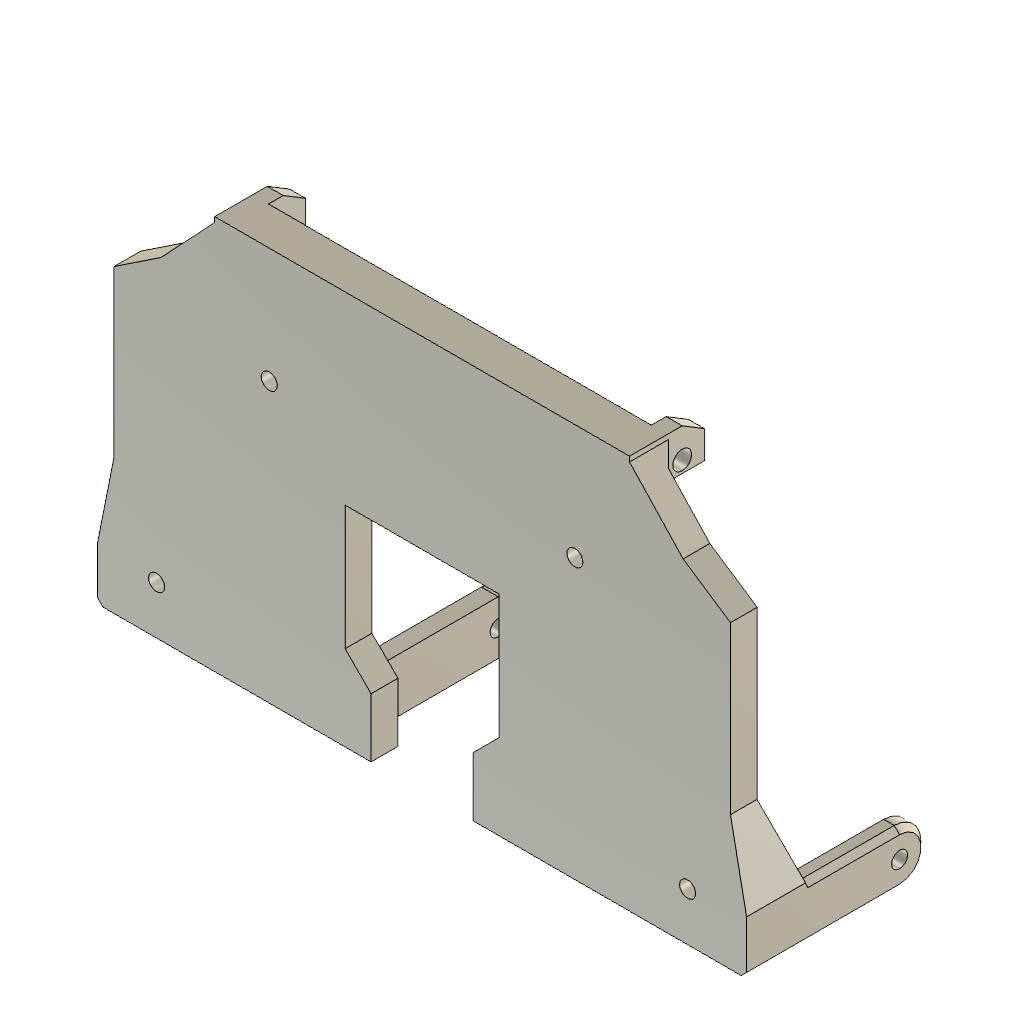
Main Base native (Autodesk Fusion 360 design; units mm, degrees)
part number: 2026-10-13-22-29-02-092
Autodesk Fusion 360 part; units mm, degrees
ref_plane "WorkPlane1" through (0, -26.0322, 0) normal (0, 1, 0) x (0, 0, 1)
sketch "Back plate" plane through (0, -26.0322, 0) normal (0, 1, 0) x (1, 0, 0)
  line L0 (-1.1848, -68.4823) -> (76.1848, -68.4823)
  line L1 (76.1848, -68.4823) -> (76.1848, -67.5429)
  line L2 (76.1848, -67.5429) -> (86.1695, -56.8868)
  line L3 (86.1695, -56.8868) -> (95.0002, -51)
  line L4 (95.0002, -51) -> (95.0002, -20)
  line L5 (95.0002, -20) -> (98.0002, -5)
  line L6 (98.0002, -5) -> (98.0002, 4)
  line L7 (98.0002, 4) -> (97.0002, 5)
  line L8 (97.0002, 5) -> (47, 5)
  line L9 (47, 5) -> (47, -6.0382)
  line L10 (47, -6.0382) -> (51.8412, -10.8794)
  line L11 (51.8412, -10.8794) -> (51.8412, -34.0592)
  line L12 (51.8412, -34.0592) -> (23.1588, -34.0592)
  line L13 (23.1588, -34.0592) -> (23.1588, -10.8794)
  line L14 (23.1588, -10.8794) -> (28, -6.0382)
  line L15 (28, -6.0382) -> (28, 5)
  line L16 (28, 5) -> (-22.0002, 5)
  line L17 (-22.0002, 5) -> (-23.0002, 4)
  line L18 (-23.0002, 4) -> (-23.0002, -5)
  line L19 (-23.0002, -5) -> (-20.0002, -20)
  line L20 (-20.0002, -20) -> (-20.0002, -51)
  line L21 (-20.0002, -51) -> (-11.1695, -56.8868)
  line L22 (-11.1695, -56.8868) -> (-1.1848, -67.5429)
  line L23 (-1.1848, -67.5429) -> (-1.1848, -68.4823)
  dimension "d159" = 1.1848
  dimension "d160" = 68.4823
  dimension "d161" = 76.1848
  dimension "d162" = 67.5429
  dimension "d163" = 86.1695
  dimension "d164" = 56.8868
  dimension "d165" = 95.0002
  dimension "d166" = 51
  dimension "d167" = 20
  dimension "d168" = 98.0002
  dimension "d169" = 5
  dimension "d170" = 4
  dimension "d171" = 97.0002
  dimension "d172" = 5
  dimension "d173" = 47
  dimension "d174" = 6.0382
  dimension "d175" = 51.8412
  dimension "d176" = 10.8794
  dimension "d177" = 34.0592
  dimension "d178" = 23.1588
  dimension "d179" = 10.8794
  dimension "d180" = 28
  dimension "d181" = 6.0382
  dimension "d182" = 5
  dimension "d183" = 22.0002
  dimension "d184" = 23.0002
  dimension "d185" = 4
  dimension "d186" = 5
  dimension "d187" = 20.0002
  dimension "d188" = 20
  dimension "d189" = 51
  dimension "d190" = 11.1695
  dimension "d191" = 56.8868
  dimension "d192" = 67.5429
  constraint horizontal L0
  constraint vertical L1
  constraint vertical L4
  constraint vertical L6
  constraint horizontal L8
  constraint vertical L9
  constraint vertical L11
  constraint horizontal L12
  constraint vertical L13
  constraint vertical L15
  constraint horizontal L16
  constraint vertical L18
  constraint vertical L20
  constraint vertical L23
  measures "d159" horizontal distance of origin L0.start
  measures "d160" vertical distance of origin L0.start
  measures "d161" horizontal distance of origin L0.end
  measures "d162" vertical distance of origin L1.end
  measures "d163" horizontal distance of origin L2.end
  measures "d164" vertical distance of origin L2.end
  measures "d165" horizontal distance of origin L3.end
  measures "d166" vertical distance of origin L3.end
  measures "d167" vertical distance of origin L4.end
  measures "d168" horizontal distance of origin L5.end
  measures "d169" vertical distance of origin L5.end
  measures "d170" vertical distance of origin L6.end
  measures "d171" horizontal distance of origin L7.end
  measures "d172" vertical distance of origin L7.end
  measures "d173" horizontal distance of origin L8.end
  measures "d174" vertical distance of origin L9.end
  measures "d175" horizontal distance of origin L10.end
  measures "d176" vertical distance of origin L10.end
  measures "d177" vertical distance of origin L11.end
  measures "d178" horizontal distance of origin L12.end
  measures "d179" vertical distance of origin L13.end
  measures "d180" horizontal distance of origin L14.end
  measures "d181" vertical distance of origin L14.end
  measures "d182" vertical distance of origin L15.end
  measures "d183" horizontal distance of origin L16.end
  measures "d184" horizontal distance of origin L17.end
  measures "d185" vertical distance of origin L17.end
  measures "d186" vertical distance of origin L18.end
  measures "d187" horizontal distance of origin L19.end
  measures "d188" vertical distance of origin L19.end
  measures "d189" vertical distance of origin L20.end
  measures "d190" horizontal distance of origin L21.end
  measures "d191" vertical distance of origin L21.end
  measures "d192" vertical distance of origin L22.end
extrude "Back plate (1)" add sketch "Back plate" along normal mid plane 5
ref_plane "WorkPlane2" through (-0.0002, 0, 0) normal (1, 0, 0) x (0, 1, 0)
sketch "Bottom bevel L" plane through (-0.0002, 0, 0) normal (1, 0, 0) x (0, 0, -1)
  line L0 (5, -26.0322) -> (2.5, -23.5322)
  line L1 (2.5, -23.5322) -> (2.5, -22.5322)
  line L2 (2.5, -22.5322) -> (6, -22.5322)
  line L3 (6, -22.5322) -> (6, -26.0322)
  line L4 (6, -26.0322) -> (5, -26.0322)
  dimension "d193" = 5
  dimension "d194" = 26.0322
  dimension "d195" = 2.5
  dimension "d196" = 23.5322
  dimension "d197" = 22.5322
  dimension "d198" = 6
  constraint vertical L1
  constraint horizontal L2
  constraint vertical L3
  constraint horizontal L4
  measures "d193" horizontal distance of origin L0.start
  measures "d194" vertical distance of origin L0.start
  measures "d195" horizontal distance of origin L0.end
  measures "d196" vertical distance of origin L0.end
  measures "d197" vertical distance of origin L1.end
  measures "d198" horizontal distance of origin L2.end
extrude "Bottom bevel L (1)" cut sketch "Bottom bevel L" along normal mid plane 34
ref_plane "WorkPlane3" through (75.0002, 0, 0) normal (1, 0, 0) x (0, 1, 0)
sketch "Bottom bevel R" plane through (75.0002, 0, 0) normal (1, 0, 0) x (0, 0, -1)
  line L0 (5, -26.0322) -> (2.5, -23.5322)
  line L1 (2.5, -23.5322) -> (2.5, -22.5322)
  line L2 (2.5, -22.5322) -> (6, -22.5322)
  line L3 (6, -22.5322) -> (6, -26.0322)
  line L4 (6, -26.0322) -> (5, -26.0322)
  dimension "d199" = 5
  dimension "d200" = 26.0322
  dimension "d201" = 2.5
  dimension "d202" = 23.5322
  dimension "d203" = 22.5322
  dimension "d204" = 6
  constraint vertical L1
  constraint horizontal L2
  constraint vertical L3
  constraint horizontal L4
  measures "d199" horizontal distance of origin L0.start
  measures "d200" vertical distance of origin L0.start
  measures "d201" horizontal distance of origin L0.end
  measures "d202" vertical distance of origin L0.end
  measures "d203" vertical distance of origin L1.end
  measures "d204" horizontal distance of origin L2.end
extrude "Bottom bevel R (1)" cut sketch "Bottom bevel R" along normal mid plane 34
ref_plane "WorkPlane4" through (-21.5002, 0, 0) normal (1, 0, 0) x (0, 1, 0)
sketch "Arm outer L" plane through (-21.5002, 0, 0) normal (1, 0, 0) x (0, 0, -1)
  line L0 (-5, -28.5322) -> (-5, 0)
  arc A0 (5, 0) -> (-5, 0) centre (0, 0) ccw
  line L1 (5, 0) -> (5, -28.5322)
  line L2 (5, -28.5322) -> (-5, -28.5322)
  dimension "d205" = 5
  dimension "d206" = 28.5322
  constraint vertical L0
  constraint vertical L1
  constraint horizontal L2
  constraint tangent L0 A0
  constraint tangent A0 L1
  constraint coincident A0.centre origin
  measures "d205" radius of A0
  measures "d206" vertical distance of A0.centre L0.start
extrude "Arm outer L (1)" add sketch "Arm outer L" along normal mid plane 3
ref_plane "WorkPlane5" through (21.5794, 0, 0) normal (1, 0, 0) x (0, 1, 0)
sketch "Arm inner L" plane through (21.5794, 0, 0) normal (1, 0, 0) x (0, 0, -1)
  line L0 (-5, -28.5322) -> (-5, 0)
  arc A0 (5, 0) -> (-5, 0) centre (0, 0) ccw
  line L1 (5, 0) -> (5, -28.5322)
  line L2 (5, -28.5322) -> (-5, -28.5322)
  dimension "d207" = 5
  dimension "d208" = 28.5322
  constraint vertical L0
  constraint vertical L1
  constraint horizontal L2
  constraint tangent L0 A0
  constraint tangent A0 L1
  constraint coincident A0.centre origin
  measures "d207" radius of A0
  measures "d208" vertical distance of A0.centre L0.start
extrude "Arm inner L (1)" add sketch "Arm inner L" along normal mid plane 3.1588
ref_plane "WorkPlane6" through (53.4206, 0, 0) normal (1, 0, 0) x (0, 1, 0)
sketch "Arm inner R" plane through (53.4206, 0, 0) normal (1, 0, 0) x (0, 0, -1)
  line L0 (-5, -28.5322) -> (-5, 0)
  arc A0 (5, 0) -> (-5, 0) centre (0, 0) ccw
  line L1 (5, 0) -> (5, -28.5322)
  line L2 (5, -28.5322) -> (-5, -28.5322)
  dimension "d209" = 5
  dimension "d210" = 28.5322
  constraint vertical L0
  constraint vertical L1
  constraint horizontal L2
  constraint tangent L0 A0
  constraint tangent A0 L1
  constraint coincident A0.centre origin
  measures "d209" radius of A0
  measures "d210" vertical distance of A0.centre L0.start
extrude "Arm inner R (1)" add sketch "Arm inner R" along normal mid plane 3.1588
ref_plane "WorkPlane7" through (96.5002, 0, 0) normal (1, 0, 0) x (0, 1, 0)
sketch "Arm outer R" plane through (96.5002, 0, 0) normal (1, 0, 0) x (0, 0, -1)
  line L0 (-5, -28.5322) -> (-5, 0)
  arc A0 (5, 0) -> (-5, 0) centre (0, 0) ccw
  line L1 (5, 0) -> (5, -28.5322)
  line L2 (5, -28.5322) -> (-5, -28.5322)
  dimension "d211" = 5
  dimension "d212" = 28.5322
  constraint vertical L0
  constraint vertical L1
  constraint horizontal L2
  constraint tangent L0 A0
  constraint tangent A0 L1
  constraint coincident A0.centre origin
  measures "d211" radius of A0
  measures "d212" vertical distance of A0.centre L0.start
extrude "Arm outer R (1)" add sketch "Arm outer R" along normal mid plane 3
ref_plane "WorkPlane8" through (0, 0, 8) normal (0, 0, 1) x (1, 0, 0)
sketch "Root outer L" plane through (0, 0, 8) normal (0, 0, 1) x (1, 0, 0)
  line L0 (-20.0002, -20.5322) -> (-14.5002, -26.0322)
  line L1 (-14.5002, -26.0322) -> (-20.0002, -26.0322)
  line L2 (-20.0002, -26.0322) -> (-20.0002, -20.5322)
  dimension "d213" = 20.0002
  dimension "d214" = 20.5322
  dimension "d215" = 14.5002
  dimension "d216" = 26.0322
  constraint horizontal L1
  constraint vertical L2
  measures "d213" horizontal distance of origin L0.start
  measures "d214" vertical distance of origin L0.start
  measures "d215" horizontal distance of origin L0.end
  measures "d216" vertical distance of origin L0.end
extrude "Root outer L (1)" add sketch "Root outer L" along normal mid plane 26
sketch "Root inner L-" plane through (0, 0, 0) normal (0, 0, 1) x (1, 0, 0)
  line L0 (20, -20.5322) -> (14.5, -26.0322)
  line L1 (14.5, -26.0322) -> (20, -26.0322)
  line L2 (20, -26.0322) -> (20, -20.5322)
  dimension "d217" = 20
  dimension "d218" = 20.5322
  dimension "d219" = 14.5
  dimension "d220" = 26.0322
  constraint horizontal L1
  constraint vertical L2
  measures "d217" horizontal distance of origin L0.start
  measures "d218" vertical distance of origin L0.start
  measures "d219" horizontal distance of origin L0.end
  measures "d220" vertical distance of origin L0.end
extrude "Root inner L- (1)" add sketch "Root inner L-" along normal mid plane 10
sketch "Root inner L+" plane through (0, 0, 0) normal (0, 0, 1) x (1, 0, 0)
  line L0 (23.1588, -20.5322) -> (28, -25.3734)
  line L1 (28, -25.3734) -> (28, -26.0322)
  line L2 (28, -26.0322) -> (23.1588, -26.0322)
  line L3 (23.1588, -26.0322) -> (23.1588, -20.5322)
  dimension "d221" = 23.1588
  dimension "d222" = 20.5322
  dimension "d223" = 28
  dimension "d224" = 25.3734
  dimension "d225" = 26.0322
  constraint vertical L1
  constraint horizontal L2
  constraint vertical L3
  measures "d221" horizontal distance of origin L0.start
  measures "d222" vertical distance of origin L0.start
  measures "d223" horizontal distance of origin L0.end
  measures "d224" vertical distance of origin L0.end
  measures "d225" vertical distance of origin L1.end
extrude "Root inner L+ (1)" add sketch "Root inner L+" along normal mid plane 10
sketch "Root inner R-" plane through (0, 0, 0) normal (0, 0, 1) x (1, 0, 0)
  line L0 (51.8412, -20.5322) -> (47, -25.3734)
  line L1 (47, -25.3734) -> (47, -26.0322)
  line L2 (47, -26.0322) -> (51.8412, -26.0322)
  line L3 (51.8412, -26.0322) -> (51.8412, -20.5322)
  dimension "d226" = 51.8412
  dimension "d227" = 20.5322
  dimension "d228" = 47
  dimension "d229" = 25.3734
  dimension "d230" = 26.0322
  constraint vertical L1
  constraint horizontal L2
  constraint vertical L3
  measures "d226" horizontal distance of origin L0.start
  measures "d227" vertical distance of origin L0.start
  measures "d228" horizontal distance of origin L0.end
  measures "d229" vertical distance of origin L0.end
  measures "d230" vertical distance of origin L1.end
extrude "Root inner R- (1)" add sketch "Root inner R-" along normal mid plane 10
sketch "Root inner R+" plane through (0, 0, 0) normal (0, 0, 1) x (1, 0, 0)
  line L0 (55, -20.5322) -> (60.5, -26.0322)
  line L1 (60.5, -26.0322) -> (55, -26.0322)
  line L2 (55, -26.0322) -> (55, -20.5322)
  dimension "d231" = 55
  dimension "d232" = 20.5322
  dimension "d233" = 60.5
  dimension "d234" = 26.0322
  constraint horizontal L1
  constraint vertical L2
  measures "d231" horizontal distance of origin L0.start
  measures "d232" vertical distance of origin L0.start
  measures "d233" horizontal distance of origin L0.end
  measures "d234" vertical distance of origin L0.end
extrude "Root inner R+ (1)" add sketch "Root inner R+" along normal mid plane 10
ref_plane "WorkPlane9" through (0, 0, 8) normal (0, 0, 1) x (1, 0, 0)
sketch "Root outer R" plane through (0, 0, 8) normal (0, 0, 1) x (1, 0, 0)
  line L0 (95.0002, -20.5322) -> (89.5002, -26.0322)
  line L1 (89.5002, -26.0322) -> (95.0002, -26.0322)
  line L2 (95.0002, -26.0322) -> (95.0002, -20.5322)
  dimension "d235" = 95.0002
  dimension "d236" = 20.5322
  dimension "d237" = 89.5002
  dimension "d238" = 26.0322
  constraint horizontal L1
  constraint vertical L2
  measures "d235" horizontal distance of origin L0.start
  measures "d236" vertical distance of origin L0.start
  measures "d237" horizontal distance of origin L0.end
  measures "d238" vertical distance of origin L0.end
extrude "Root outer R (1)" add sketch "Root outer R" along normal mid plane 26
ref_plane "WorkPlane10" through (0, -20.7822, 0) normal (0, 1, 0) x (0, 0, 1)
sketch "Gusset L" plane through (0, -20.7822, 0) normal (0, 1, 0) x (1, 0, 0)
  line L0 (-23.0002, -5) -> (-20.0002, -20)
  line L1 (-20.0002, -20) -> (-20.0002, -4)
  line L2 (-20.0002, -4) -> (-23.0002, -4)
  line L3 (-23.0002, -4) -> (-23.0002, -5)
  dimension "d239" = 23.0002
  dimension "d240" = 5
  dimension "d241" = 20.0002
  dimension "d242" = 20
  dimension "d243" = 4
  constraint vertical L1
  constraint horizontal L2
  constraint vertical L3
  measures "d239" horizontal distance of origin L0.start
  measures "d240" vertical distance of origin L0.start
  measures "d241" horizontal distance of origin L0.end
  measures "d242" vertical distance of origin L0.end
  measures "d243" vertical distance of origin L1.end
extrude "Gusset L (1)" add sketch "Gusset L" along normal mid plane 6.5
ref_plane "WorkPlane11" through (0, -20.7822, 0) normal (0, 1, 0) x (0, 0, 1)
sketch "Gusset R" plane through (0, -20.7822, 0) normal (0, 1, 0) x (1, 0, 0)
  line L0 (98.0002, -5) -> (98.0002, -4)
  line L1 (98.0002, -4) -> (95.0002, -4)
  line L2 (95.0002, -4) -> (95.0002, -20)
  line L3 (95.0002, -20) -> (98.0002, -5)
  dimension "d244" = 98.0002
  dimension "d245" = 5
  dimension "d246" = 4
  dimension "d247" = 95.0002
  dimension "d248" = 20
  constraint vertical L0
  constraint horizontal L1
  constraint vertical L2
  measures "d244" horizontal distance of origin L0.start
  measures "d245" vertical distance of origin L0.start
  measures "d246" vertical distance of origin L0.end
  measures "d247" horizontal distance of origin L1.end
  measures "d248" vertical distance of origin L2.end
extrude "Gusset R (1)" add sketch "Gusset R" along normal mid plane 6.5
ref_plane "WorkPlane12" through (-20, 0, 0) normal (1, 0, 0) x (0, 1, 0)
sketch "Gusset plane L" plane through (-20, 0, 0) normal (1, 0, 0) x (0, 0, -1)
  line L0 (-19.9, -23.5322) -> (-5, -17.5322)
  line L1 (-5, -17.5322) -> (-5, -16.5322)
  line L2 (-5, -16.5322) -> (-22, -16.5322)
  line L3 (-22, -16.5322) -> (-22, -23.5322)
  line L4 (-22, -23.5322) -> (-19.9, -23.5322)
  dimension "d249" = 19.9
  dimension "d250" = 23.5322
  dimension "d251" = 5
  dimension "d252" = 17.5322
  dimension "d253" = 16.5322
  dimension "d254" = 22
  constraint vertical L1
  constraint horizontal L2
  constraint vertical L3
  constraint horizontal L4
  measures "d249" horizontal distance of origin L0.start
  measures "d250" vertical distance of origin L0.start
  measures "d251" horizontal distance of origin L0.end
  measures "d252" vertical distance of origin L0.end
  measures "d253" vertical distance of origin L1.end
  measures "d254" horizontal distance of origin L2.end
extrude "Gusset plane L (1)" cut sketch "Gusset plane L" along normal mid plane 8
ref_plane "WorkPlane13" through (95, 0, 0) normal (1, 0, 0) x (0, 1, 0)
sketch "Gusset plane R" plane through (95, 0, 0) normal (1, 0, 0) x (0, 0, -1)
  line L0 (-19.9, -23.5322) -> (-5, -17.5322)
  line L1 (-5, -17.5322) -> (-5, -16.5322)
  line L2 (-5, -16.5322) -> (-22, -16.5322)
  line L3 (-22, -16.5322) -> (-22, -23.5322)
  line L4 (-22, -23.5322) -> (-19.9, -23.5322)
  dimension "d255" = 19.9
  dimension "d256" = 23.5322
  dimension "d257" = 5
  dimension "d258" = 17.5322
  dimension "d259" = 16.5322
  dimension "d260" = 22
  constraint vertical L1
  constraint horizontal L2
  constraint vertical L3
  constraint horizontal L4
  measures "d255" horizontal distance of origin L0.start
  measures "d256" vertical distance of origin L0.start
  measures "d257" horizontal distance of origin L0.end
  measures "d258" vertical distance of origin L0.end
  measures "d259" vertical distance of origin L1.end
  measures "d260" horizontal distance of origin L2.end
extrude "Gusset plane R (1)" cut sketch "Gusset plane R" along normal mid plane 8
chamfer "Outer chamfer L" distance 1 angle 45 3 edges at (-23.0002, 5, 0) (-23.0002, -14.2661, -5) (-23.0002, -8.7661, 5) tangent chain off
chamfer "Outer chamfer R" distance 1 angle 45 3 edges at (98.0002, 5, 0) (98.0002, -8.7661, 5) (98.0002, -14.2661, -5) tangent chain off
ref_plane "WorkPlane14" through (0, -22.7528, 0) normal (0, 1, 0) x (0, 0, 1)
sketch "Block" plane through (0, -22.7528, 0) normal (0, 1, 0) x (1, 0, 0)
  line L0 (-1.1848, -68.4823) -> (76.1848, -68.4823)
  line L1 (76.1848, -68.4823) -> (76.1848, -34.7038)
  line L2 (76.1848, -34.7038) -> (73.8848, -34.7038)
  line L3 (73.8848, -34.7038) -> (73.8848, -24)
  line L4 (73.8848, -24) -> (64.8848, -24)
  line L5 (64.8848, -24) -> (64.8848, -34.0592)
  line L6 (64.8848, -34.0592) -> (10.1152, -34.0592)
  line L7 (10.1152, -34.0592) -> (10.1152, -24)
  line L8 (10.1152, -24) -> (-1.1848, -24)
  line L9 (-1.1848, -24) -> (-1.1848, -68.4823)
  dimension "d261" = 1.1848
  dimension "d262" = 68.4823
  dimension "d263" = 76.1848
  dimension "d264" = 34.7038
  dimension "d265" = 73.8848
  dimension "d266" = 24
  dimension "d267" = 64.8848
  dimension "d268" = 34.0592
  dimension "d269" = 10.1152
  dimension "d270" = 24
  constraint horizontal L0
  constraint vertical L1
  constraint horizontal L2
  constraint vertical L3
  constraint horizontal L4
  constraint vertical L5
  constraint horizontal L6
  constraint vertical L7
  constraint horizontal L8
  constraint vertical L9
  measures "d261" horizontal distance of origin L0.start
  measures "d262" vertical distance of origin L0.start
  measures "d263" horizontal distance of origin L0.end
  measures "d264" vertical distance of origin L1.end
  measures "d265" horizontal distance of origin L2.end
  measures "d266" vertical distance of origin L3.end
  measures "d267" horizontal distance of origin L4.end
  measures "d268" vertical distance of origin L5.end
  measures "d269" horizontal distance of origin L6.end
  measures "d270" vertical distance of origin L7.end
extrude "Block (1)" add sketch "Block" along normal mid plane 2.5589
ref_plane "WorkPlane15" through (4.5, 0, 0) normal (1, 0, 0) x (0, 1, 0)
sketch "Block chamfer L" plane through (4.5, 0, 0) normal (1, 0, 0) x (0, 0, -1)
  line L0 (-27, -21.4733) -> (-24.9682, -23.5322)
  line L1 (-24.9682, -23.5322) -> (-20, -23.5322)
  line L2 (-20, -23.5322) -> (-20, -21.4733)
  line L3 (-20, -21.4733) -> (-27, -21.4733)
  dimension "d271" = 27
  dimension "d272" = 21.4733
  dimension "d273" = 24.9682
  dimension "d274" = 23.5322
  dimension "d275" = 20
  constraint horizontal L1
  constraint vertical L2
  constraint horizontal L3
  measures "d271" horizontal distance of origin L0.start
  measures "d272" vertical distance of origin L0.start
  measures "d273" horizontal distance of origin L0.end
  measures "d274" vertical distance of origin L0.end
  measures "d275" horizontal distance of origin L1.end
extrude "Block chamfer L (1)" cut sketch "Block chamfer L" along normal mid plane 13
ref_plane "WorkPlane16" through (69.25, 0, 0) normal (1, 0, 0) x (0, 1, 0)
sketch "Block chamfer R" plane through (69.25, 0, 0) normal (1, 0, 0) x (0, 0, -1)
  line L0 (-27, -21.4733) -> (-24.9682, -23.5322)
  line L1 (-24.9682, -23.5322) -> (-20, -23.5322)
  line L2 (-20, -23.5322) -> (-20, -21.4733)
  line L3 (-20, -21.4733) -> (-27, -21.4733)
  dimension "d276" = 27
  dimension "d277" = 21.4733
  dimension "d278" = 24.9682
  dimension "d279" = 23.5322
  dimension "d280" = 20
  constraint horizontal L1
  constraint vertical L2
  constraint horizontal L3
  measures "d276" horizontal distance of origin L0.start
  measures "d277" vertical distance of origin L0.start
  measures "d278" horizontal distance of origin L0.end
  measures "d279" vertical distance of origin L0.end
  measures "d280" horizontal distance of origin L1.end
extrude "Block chamfer R (1)" cut sketch "Block chamfer R" along normal mid plane 10.5
ref_plane "WorkPlane17" through (0, -22.6572, 0) normal (0, 1, 0) x (0, 0, 1)
sketch "Gusset upper L" plane through (0, -22.6572, 0) normal (0, 1, 0) x (1, 0, 0)
  line L0 (-3.6, -34.7038) -> (-0.6848, -34.7038)
  line L1 (-0.6848, -34.7038) -> (-0.6848, -68.4823)
  line L2 (-0.6848, -68.4823) -> (-1.1848, -68.4823)
  line L3 (-1.1848, -68.4823) -> (-1.1848, -67.5429)
  line L4 (-1.1848, -67.5429) -> (-3.6, -64.9653)
  line L5 (-3.6, -64.9653) -> (-3.6, -34.7038)
  dimension "d281" = 3.6
  dimension "d282" = 34.7038
  dimension "d283" = 0.6848
  dimension "d284" = 68.4823
  dimension "d285" = 1.1848
  dimension "d286" = 67.5429
  dimension "d287" = 64.9653
  constraint horizontal L0
  constraint vertical L1
  constraint horizontal L2
  constraint vertical L3
  constraint vertical L5
  measures "d281" horizontal distance of origin L0.start
  measures "d282" vertical distance of origin L0.start
  measures "d283" horizontal distance of origin L0.end
  measures "d284" vertical distance of origin L1.end
  measures "d285" horizontal distance of origin L2.end
  measures "d286" vertical distance of origin L3.end
  measures "d287" vertical distance of origin L4.end
extrude "Gusset upper L (1)" add sketch "Gusset upper L" along normal mid plane 2.75
ref_plane "WorkPlane18" through (-2.1924, 0, 0) normal (1, 0, 0) x (0, 1, 0)
sketch "Gusset lower L" plane through (-2.1924, 0, 0) normal (1, 0, 0) x (0, 0, -1)
  line L0 (-28.0263, -24.0322) -> (-28.037, -21.0322)
  line L1 (-28.037, -21.0322) -> (-34.7038, -21.0322)
  line L2 (-34.7038, -21.0322) -> (-34.7038, -24.0322)
  line L3 (-34.7038, -24.0322) -> (-28.0263, -24.0322)
  dimension "d288" = 28.0263
  dimension "d289" = 24.0322
  dimension "d290" = 28.037
  dimension "d291" = 21.0322
  dimension "d292" = 34.7038
  constraint horizontal L1
  constraint vertical L2
  constraint horizontal L3
  measures "d288" horizontal distance of origin L0.start
  measures "d289" vertical distance of origin L0.start
  measures "d290" horizontal distance of origin L0.end
  measures "d291" vertical distance of origin L0.end
  measures "d292" horizontal distance of origin L1.end
extrude "Gusset lower L (1)" add sketch "Gusset lower L" along normal mid plane 3.0152
ref_plane "WorkPlane19" through (0, 0, 51.8519) normal (0, 0, 1) x (1, 0, 0)
sketch "Gusset upper taper L" plane through (0, 0, 51.8519) normal (0, 0, 1) x (1, 0, 0)
  line L0 (-3.4348, -23.5322) -> (-1.1848, -21.2822)
  line L1 (-1.1848, -21.2822) -> (-1.1848, -21.4733)
  line L2 (-1.1848, -21.4733) -> (-0.5, -21.4733)
  line L3 (-0.5, -21.4733) -> (-0.5, -21)
  line L4 (-0.5, -21) -> (-5, -21)
  line L5 (-5, -21) -> (-5, -23.5322)
  line L6 (-5, -23.5322) -> (-3.4348, -23.5322)
  dimension "d293" = 3.4348
  dimension "d294" = 23.5322
  dimension "d295" = 1.1848
  dimension "d296" = 21.2822
  dimension "d297" = 21.4733
  dimension "d298" = 0.5
  dimension "d299" = 21
  dimension "d300" = 5
  constraint vertical L1
  constraint horizontal L2
  constraint vertical L3
  constraint horizontal L4
  constraint vertical L5
  constraint horizontal L6
  measures "d293" horizontal distance of origin L0.start
  measures "d294" vertical distance of origin L0.start
  measures "d295" horizontal distance of origin L0.end
  measures "d296" vertical distance of origin L0.end
  measures "d297" vertical distance of origin L1.end
  measures "d298" horizontal distance of origin L2.end
  measures "d299" vertical distance of origin L3.end
  measures "d300" horizontal distance of origin L4.end
extrude "Gusset upper taper L (1)" cut sketch "Gusset upper taper L" along normal mid plane 34.2962
ref_plane "WorkPlane20" through (0, 0, 30.8519) normal (0, 0, 1) x (1, 0, 0)
sketch "Gusset lower taper L" plane through (0, 0, 30.8519) normal (0, 0, 1) x (1, 0, 0)
  line L0 (-3.6848, -23.5322) -> (-1.1848, -21.0322)
  line L1 (-1.1848, -21.0322) -> (-1.1848, -20.5)
  line L2 (-1.1848, -20.5) -> (-5, -20.5)
  line L3 (-5, -20.5) -> (-5, -23.5322)
  line L4 (-5, -23.5322) -> (-3.6848, -23.5322)
  dimension "d301" = 3.6848
  dimension "d302" = 23.5322
  dimension "d303" = 1.1848
  dimension "d304" = 21.0322
  dimension "d305" = 20.5
  dimension "d306" = 5
  constraint vertical L1
  constraint horizontal L2
  constraint vertical L3
  constraint horizontal L4
  measures "d301" horizontal distance of origin L0.start
  measures "d302" vertical distance of origin L0.start
  measures "d303" horizontal distance of origin L0.end
  measures "d304" vertical distance of origin L0.end
  measures "d305" vertical distance of origin L1.end
  measures "d306" horizontal distance of origin L2.end
extrude "Gusset lower taper L (1)" cut sketch "Gusset lower taper L" along normal mid plane 7.7038
ref_plane "WorkPlane21" through (0.3152, 0, 0) normal (1, 0, 0) x (0, 1, 0)
sketch "Post upper L" plane through (0.3152, 0, 0) normal (1, 0, 0) x (0, 0, -1)
  line L0 (-60.7428, -21.9733) -> (-60.7428, -14.5294)
  line L1 (-60.7428, -14.5294) -> (-65.9301, -14.5294)
  line L2 (-65.9301, -14.5294) -> (-68.4823, -18.7258)
  line L3 (-68.4823, -18.7258) -> (-68.4823, -21.9733)
  line L4 (-68.4823, -21.9733) -> (-60.7428, -21.9733)
  dimension "d307" = 60.7428
  dimension "d308" = 21.9733
  dimension "d309" = 14.5294
  dimension "d310" = 65.9301
  dimension "d311" = 68.4823
  dimension "d312" = 18.7258
  constraint vertical L0
  constraint horizontal L1
  constraint vertical L3
  constraint horizontal L4
  measures "d307" horizontal distance of origin L0.start
  measures "d308" vertical distance of origin L0.start
  measures "d309" vertical distance of origin L0.end
  measures "d310" horizontal distance of origin L1.end
  measures "d311" horizontal distance of origin L2.end
  measures "d312" vertical distance of origin L2.end
extrude "Post upper L (1)" add sketch "Post upper L" along normal mid plane 3
ref_plane "WorkPlane22" through (0.3152, 0, 0) normal (1, 0, 0) x (0, 1, 0)
sketch "Post lower L" plane through (0.3152, 0, 0) normal (1, 0, 0) x (0, 0, -1)
  line L0 (-28.0263, -24.0322) -> (-28.0592, -14.7733)
  line L1 (-28.0592, -14.7733) -> (-32.0592, -14.7733)
  line L2 (-32.0592, -14.7733) -> (-34.7038, -16.5105)
  line L3 (-34.7038, -16.5105) -> (-34.7038, -24.0322)
  line L4 (-34.7038, -24.0322) -> (-28.0263, -24.0322)
  dimension "d313" = 28.0263
  dimension "d314" = 24.0322
  dimension "d315" = 28.0592
  dimension "d316" = 14.7733
  dimension "d317" = 32.0592
  dimension "d318" = 34.7038
  dimension "d319" = 16.5105
  constraint horizontal L1
  constraint vertical L3
  constraint horizontal L4
  measures "d313" horizontal distance of origin L0.start
  measures "d314" vertical distance of origin L0.start
  measures "d315" horizontal distance of origin L0.end
  measures "d316" vertical distance of origin L0.end
  measures "d317" horizontal distance of origin L1.end
  measures "d318" horizontal distance of origin L2.end
  measures "d319" vertical distance of origin L2.end
extrude "Post lower L (1)" add sketch "Post lower L" along normal mid plane 3
ref_plane "WorkPlane23" through (0.3152, 0, 0) normal (1, 0, 0) x (0, 1, 0)
sketch "Post hole upper L" plane through (0.3152, 0, 0) normal (1, 0, 0) x (0, 0, -1)
  circle A0 centre (-62.9667, -18.7303) radius 1.75
  dimension "d320" = 3.5
  dimension "d321" = 62.9667
  dimension "d322" = 18.7303
  measures "d320" diameter of A0
  measures "d321" horizontal distance of origin A0.centre
  measures "d322" vertical distance of origin A0.centre
extrude "Post hole upper L (1)" cut sketch "Post hole upper L" along normal mid plane 4
ref_plane "WorkPlane24" through (0.3152, 0, 0) normal (1, 0, 0) x (0, 1, 0)
sketch "Post hole lower L" plane through (0.3152, 0, 0) normal (1, 0, 0) x (0, 0, -1)
  circle A0 centre (-31, -18) radius 1.75
  dimension "d323" = 3.5
  dimension "d324" = 31
  dimension "d325" = 18
  measures "d323" diameter of A0
  measures "d324" horizontal distance of origin A0.centre
  measures "d325" vertical distance of origin A0.centre
extrude "Post hole lower L (1)" cut sketch "Post hole lower L" along normal mid plane 4
ref_plane "WorkPlane25" through (0, -22.6572, 0) normal (0, 1, 0) x (0, 0, 1)
sketch "Gusset upper R" plane through (0, -22.6572, 0) normal (0, 1, 0) x (1, 0, 0)
  line L0 (78.6, -64.9653) -> (76.1848, -67.5429)
  line L1 (76.1848, -67.5429) -> (76.1848, -68.4823)
  line L2 (76.1848, -68.4823) -> (75.6848, -68.4823)
  line L3 (75.6848, -68.4823) -> (75.6848, -34.7038)
  line L4 (75.6848, -34.7038) -> (78.6, -34.7038)
  line L5 (78.6, -34.7038) -> (78.6, -64.9653)
  dimension "d326" = 78.6
  dimension "d327" = 64.9653
  dimension "d328" = 76.1848
  dimension "d329" = 67.5429
  dimension "d330" = 68.4823
  dimension "d331" = 75.6848
  dimension "d332" = 34.7038
  constraint vertical L1
  constraint horizontal L2
  constraint vertical L3
  constraint horizontal L4
  constraint vertical L5
  measures "d326" horizontal distance of origin L0.start
  measures "d327" vertical distance of origin L0.start
  measures "d328" horizontal distance of origin L0.end
  measures "d329" vertical distance of origin L0.end
  measures "d330" vertical distance of origin L1.end
  measures "d331" horizontal distance of origin L2.end
  measures "d332" vertical distance of origin L3.end
extrude "Gusset upper R (1)" add sketch "Gusset upper R" along normal mid plane 2.75
ref_plane "WorkPlane26" through (77.1924, 0, 0) normal (1, 0, 0) x (0, 1, 0)
sketch "Gusset lower R" plane through (77.1924, 0, 0) normal (1, 0, 0) x (0, 0, -1)
  line L0 (-28.0263, -24.0322) -> (-28.037, -21.0322)
  line L1 (-28.037, -21.0322) -> (-34.7038, -21.0322)
  line L2 (-34.7038, -21.0322) -> (-34.7038, -24.0322)
  line L3 (-34.7038, -24.0322) -> (-28.0263, -24.0322)
  dimension "d333" = 28.0263
  dimension "d334" = 24.0322
  dimension "d335" = 28.037
  dimension "d336" = 21.0322
  dimension "d337" = 34.7038
  constraint horizontal L1
  constraint vertical L2
  constraint horizontal L3
  measures "d333" horizontal distance of origin L0.start
  measures "d334" vertical distance of origin L0.start
  measures "d335" horizontal distance of origin L0.end
  measures "d336" vertical distance of origin L0.end
  measures "d337" horizontal distance of origin L1.end
extrude "Gusset lower R (1)" add sketch "Gusset lower R" along normal mid plane 3.0152
ref_plane "WorkPlane27" through (0, 0, 51.8519) normal (0, 0, 1) x (1, 0, 0)
sketch "Gusset upper taper R" plane through (0, 0, 51.8519) normal (0, 0, 1) x (1, 0, 0)
  line L0 (80, -23.5322) -> (80, -21)
  line L1 (80, -21) -> (75.5, -21)
  line L2 (75.5, -21) -> (75.5, -21.4733)
  line L3 (75.5, -21.4733) -> (76.1848, -21.4733)
  line L4 (76.1848, -21.4733) -> (76.1848, -21.2822)
  line L5 (76.1848, -21.2822) -> (78.4348, -23.5322)
  line L6 (78.4348, -23.5322) -> (80, -23.5322)
  dimension "d338" = 80
  dimension "d339" = 23.5322
  dimension "d340" = 21
  dimension "d341" = 75.5
  dimension "d342" = 21.4733
  dimension "d343" = 76.1848
  dimension "d344" = 21.2822
  dimension "d345" = 78.4348
  constraint vertical L0
  constraint horizontal L1
  constraint vertical L2
  constraint horizontal L3
  constraint vertical L4
  constraint horizontal L6
  measures "d338" horizontal distance of origin L0.start
  measures "d339" vertical distance of origin L0.start
  measures "d340" vertical distance of origin L0.end
  measures "d341" horizontal distance of origin L1.end
  measures "d342" vertical distance of origin L2.end
  measures "d343" horizontal distance of origin L3.end
  measures "d344" vertical distance of origin L4.end
  measures "d345" horizontal distance of origin L5.end
extrude "Gusset upper taper R (1)" cut sketch "Gusset upper taper R" along normal mid plane 34.2962
ref_plane "WorkPlane28" through (0, 0, 30.8519) normal (0, 0, 1) x (1, 0, 0)
sketch "Gusset lower taper R" plane through (0, 0, 30.8519) normal (0, 0, 1) x (1, 0, 0)
  line L0 (80, -23.5322) -> (80, -20.5)
  line L1 (80, -20.5) -> (76.1848, -20.5)
  line L2 (76.1848, -20.5) -> (76.1848, -21.0322)
  line L3 (76.1848, -21.0322) -> (78.6848, -23.5322)
  line L4 (78.6848, -23.5322) -> (80, -23.5322)
  dimension "d346" = 80
  dimension "d347" = 23.5322
  dimension "d348" = 20.5
  dimension "d349" = 76.1848
  dimension "d350" = 21.0322
  dimension "d351" = 78.6848
  constraint vertical L0
  constraint horizontal L1
  constraint vertical L2
  constraint horizontal L4
  measures "d346" horizontal distance of origin L0.start
  measures "d347" vertical distance of origin L0.start
  measures "d348" vertical distance of origin L0.end
  measures "d349" horizontal distance of origin L1.end
  measures "d350" vertical distance of origin L2.end
  measures "d351" horizontal distance of origin L3.end
extrude "Gusset lower taper R (1)" cut sketch "Gusset lower taper R" along normal mid plane 7.7038
ref_plane "WorkPlane29" through (74.6848, 0, 0) normal (1, 0, 0) x (0, 1, 0)
sketch "Post upper R" plane through (74.6848, 0, 0) normal (1, 0, 0) x (0, 0, -1)
  line L0 (-60.7428, -21.9733) -> (-60.7428, -14.5294)
  line L1 (-60.7428, -14.5294) -> (-65.9301, -14.5294)
  line L2 (-65.9301, -14.5294) -> (-68.4823, -18.7258)
  line L3 (-68.4823, -18.7258) -> (-68.4823, -21.9733)
  line L4 (-68.4823, -21.9733) -> (-60.7428, -21.9733)
  dimension "d352" = 60.7428
  dimension "d353" = 21.9733
  dimension "d354" = 14.5294
  dimension "d355" = 65.9301
  dimension "d356" = 68.4823
  dimension "d357" = 18.7258
  constraint vertical L0
  constraint horizontal L1
  constraint vertical L3
  constraint horizontal L4
  measures "d352" horizontal distance of origin L0.start
  measures "d353" vertical distance of origin L0.start
  measures "d354" vertical distance of origin L0.end
  measures "d355" horizontal distance of origin L1.end
  measures "d356" horizontal distance of origin L2.end
  measures "d357" vertical distance of origin L2.end
extrude "Post upper R (1)" add sketch "Post upper R" along normal mid plane 3
ref_plane "WorkPlane30" through (74.6848, 0, 0) normal (1, 0, 0) x (0, 1, 0)
sketch "Post lower R" plane through (74.6848, 0, 0) normal (1, 0, 0) x (0, 0, -1)
  line L0 (-28.0263, -24.0322) -> (-28.0592, -14.7733)
  line L1 (-28.0592, -14.7733) -> (-32.0592, -14.7733)
  line L2 (-32.0592, -14.7733) -> (-34.7038, -16.5105)
  line L3 (-34.7038, -16.5105) -> (-34.7038, -24.0322)
  line L4 (-34.7038, -24.0322) -> (-28.0263, -24.0322)
  dimension "d358" = 28.0263
  dimension "d359" = 24.0322
  dimension "d360" = 28.0592
  dimension "d361" = 14.7733
  dimension "d362" = 32.0592
  dimension "d363" = 34.7038
  dimension "d364" = 16.5105
  constraint horizontal L1
  constraint vertical L3
  constraint horizontal L4
  measures "d358" horizontal distance of origin L0.start
  measures "d359" vertical distance of origin L0.start
  measures "d360" horizontal distance of origin L0.end
  measures "d361" vertical distance of origin L0.end
  measures "d362" horizontal distance of origin L1.end
  measures "d363" horizontal distance of origin L2.end
  measures "d364" vertical distance of origin L2.end
extrude "Post lower R (1)" add sketch "Post lower R" along normal mid plane 3
ref_plane "WorkPlane31" through (74.6848, 0, 0) normal (1, 0, 0) x (0, 1, 0)
sketch "Post hole upper R" plane through (74.6848, 0, 0) normal (1, 0, 0) x (0, 0, -1)
  circle A0 centre (-62.9667, -18.7303) radius 1.75
  dimension "d365" = 3.5
  dimension "d366" = 62.9667
  dimension "d367" = 18.7303
  measures "d365" diameter of A0
  measures "d366" horizontal distance of origin A0.centre
  measures "d367" vertical distance of origin A0.centre
extrude "Post hole upper R (1)" cut sketch "Post hole upper R" along normal mid plane 4
ref_plane "WorkPlane32" through (74.6848, 0, 0) normal (1, 0, 0) x (0, 1, 0)
sketch "Post hole lower R" plane through (74.6848, 0, 0) normal (1, 0, 0) x (0, 0, -1)
  circle A0 centre (-31, -18) radius 1.75
  dimension "d368" = 3.5
  dimension "d369" = 31
  dimension "d370" = 18
  measures "d368" diameter of A0
  measures "d369" horizontal distance of origin A0.centre
  measures "d370" vertical distance of origin A0.centre
extrude "Post hole lower R (1)" cut sketch "Post hole lower R" along normal mid plane 4
ref_plane "WorkPlane33" through (37.5, 0, 0) normal (1, 0, 0) x (0, 1, 0)
sketch "Pivot holes" plane through (37.5, 0, 0) normal (1, 0, 0) x (0, 0, -1)
  circle A0 centre (0, 0) radius 1.5
  dimension "d371" = 3
  constraint coincident A0.centre origin
  measures "d371" diameter of A0
extrude "Pivot holes (1)" cut sketch "Pivot holes" along normal mid plane 123
ref_plane "WorkPlane34" through (0, -26.0322, 0) normal (0, 1, 0) x (0, 0, 1)
sketch "Plate hole BL" plane through (0, -26.0322, 0) normal (0, 1, 0) x (1, 0, 0)
  circle A0 centre (-12, -4) radius 1.5
  dimension "d372" = 3
  dimension "d373" = 12
  dimension "d374" = 4
  measures "d372" diameter of A0
  measures "d373" horizontal distance of origin A0.centre
  measures "d374" vertical distance of origin A0.centre
extrude "Plate hole BL (1)" cut sketch "Plate hole BL" along normal mid plane 5
ref_plane "WorkPlane35" through (0, -26.0322, 0) normal (0, 1, 0) x (0, 0, 1)
sketch "Plate hole BR" plane through (0, -26.0322, 0) normal (0, 1, 0) x (1, 0, 0)
  circle A0 centre (87, -4) radius 1.5
  dimension "d375" = 3
  dimension "d376" = 87
  dimension "d377" = 4
  measures "d375" diameter of A0
  measures "d376" horizontal distance of origin A0.centre
  measures "d377" vertical distance of origin A0.centre
extrude "Plate hole BR (1)" cut sketch "Plate hole BR" along normal mid plane 5
ref_plane "WorkPlane36" through (0, -25.0028, 0) normal (0, 1, 0) x (0, 0, 1)
sketch "Plate hole TL" plane through (0, -25.0028, 0) normal (0, 1, 0) x (1, 0, 0)
  circle A0 centre (9, -47) radius 1.5
  dimension "d378" = 3
  dimension "d379" = 9
  dimension "d380" = 47
  measures "d378" diameter of A0
  measures "d379" horizontal distance of origin A0.centre
  measures "d380" vertical distance of origin A0.centre
extrude "Plate hole TL (1)" cut sketch "Plate hole TL" along normal mid plane 7.0589
ref_plane "WorkPlane37" through (0, -25.0028, 0) normal (0, 1, 0) x (0, 0, 1)
sketch "Plate hole TR" plane through (0, -25.0028, 0) normal (0, 1, 0) x (1, 0, 0)
  circle A0 centre (66, -47) radius 1.5
  dimension "d381" = 3
  dimension "d382" = 66
  dimension "d383" = 47
  measures "d381" diameter of A0
  measures "d382" horizontal distance of origin A0.centre
  measures "d383" vertical distance of origin A0.centre
extrude "Plate hole TR (1)" cut sketch "Plate hole TR" along normal mid plane 7.0589
named bodies: "Main Base native"
